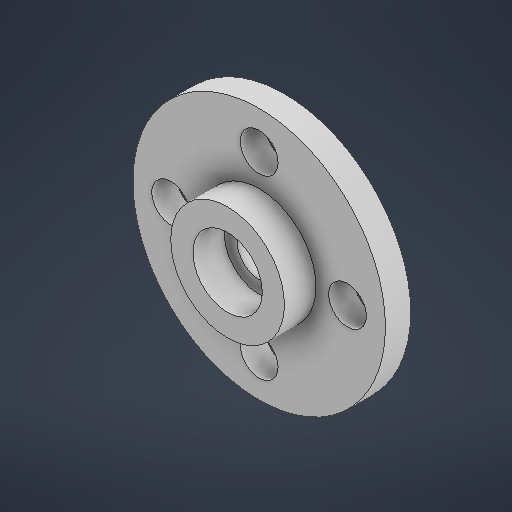
# Autodesk Inventor part: Pieza6
Saved by Autodesk Inventor 2027 (Build 310192060, 192F)
## iProperties
Created: 2026-09-18
Part Number: Pieza6
Material: Genérico
Document SubType Name: Modeling
Designer: alexa
Density: 1 g/cm^3
Appearance: Valor por defecto
Project: STAR TRACKER
Author: alexa
Title: Disco metálico 25t
Autodesk Inventor part; units mm, degrees
ref_plane "YZ Plane" through (0, 0, 0) normal (1, 0, 0) x (0, 1, 0)
ref_plane "XZ Plane" through (0, 0, 0) normal (0, 1, 0) x (-1, 0, 0)
ref_plane "XY Plane" through (0, 0, 0) normal (0, 0, 1) x (1, 0, 0)
sketch "Boceto1" plane through (0, 0, 0) normal (0, 0, 1) x (1, 0, 0)
  circle A0 centre (0, 0) radius 10
  circle A1 centre (0, 0) radius 2.75
  line L0 (7, 0) -> (-7, 0)
  line L1 (0, -7) -> (0, 7)
  circle A2 centre (7, 0) radius 1.5
  circle A3 centre (0, -7) radius 1.5
  circle A4 centre (-7, 0) radius 1.5
  circle A5 centre (0, 7) radius 1.5
  circle A6 centre (0, 0) radius 4.5
  circle A7 centre (0, 0) radius 1.75
  dimension "d0" = 20
  dimension "d1" = 5.5
  dimension "d2" = 14
  dimension "d3" = 14
  dimension "d4" = 3
  dimension "d5" = 3
  dimension "d6" = 3
  dimension "d7" = 3
  dimension "d10" = 9
  dimension "d13" = 3.5
  constraints: 9 coincident, 8 centre point, 4 end point, 2 midpoint, 1 horizontal, 1 vertical
  measures "d0" diameter of A0
  measures "d1" diameter of A1
  measures "d2" distance of L0.start L0.end
  measures "d3" distance of L1.start L1.end
  measures "d4" diameter of A2
  measures "d5" diameter of A3
  measures "d6" diameter of A4
  measures "d7" diameter of A5
  measures "d10" diameter of A6
  measures "d13" diameter of A7
extrude "Extrusión1" add sketch "Boceto1" along normal blind 2 contours A0 | L0 A7 L1 A1 | L0 A6 L1 A1 | A1 L1 A6 L0 | A1 L1 A7 L0 | L1 A7 L0 A1 | A1 L0 A6 L1 | L1 A6 L0 A1 | A1 L0 A7 L1
extrude "Extrusión2" add sketch "Boceto1" along normal blind 4.5 contours L0 A6 L1 A1 | A1 L1 A6 L0 | A1 L0 A6 L1 | L1 A6 L0 A1
